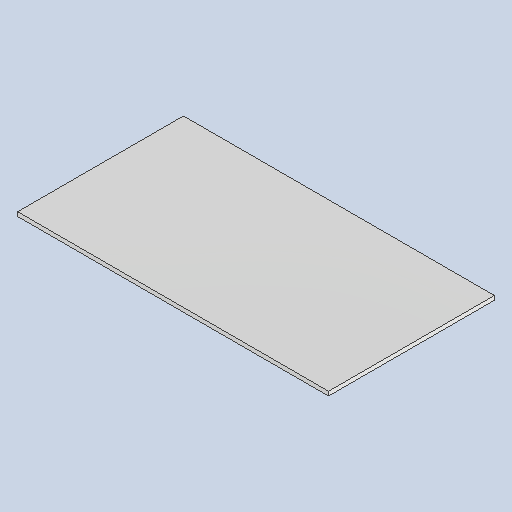
# Autodesk Inventor part: RDS-5002 Panel Plate 750x400
Saved by Autodesk Inventor 2026.2 (Build 302298000, 298)
## iProperties
Created: 2024-04-04
Part Number: RDS-5002 Panel Plate 750x400
Material: PVC, Unplasticized
Document SubType Name: Modeling
Designer: admin
Density: 1.29 g/cm^3
Appearance: Smooth - White
Mass: 3870 g
Surface Area: 6230 cm^2
Volume: 3000 cm^3
Stock Number: Пластина панельная (СДР 083)
Author: admin
Autodesk Inventor part; units mm, degrees
ref_plane "YZ Plane" through (0, 0, 0) normal (1, 0, 0) x (0, 1, 0)
ref_plane "XZ Plane" through (0, 0, 0) normal (0, 1, 0) x (-1, 0, 0)
ref_plane "XY Plane" through (0, 0, 0) normal (0, 0, 1) x (1, 0, 0)
sketch "Sketch1" plane through (0, 0, 0) normal (0, 0, 1) x (1, 0, 0)
  line L0 (-375, 200) -> (375, 200)
  line L1 (375, 200) -> (375, -200)
  line L2 (375, -200) -> (-375, -200)
  line L3 (-375, -200) -> (-375, 200)
  line L4 (-375, 200) -> (375, -200) construction
  line L5 (375, 200) -> (-375, -200) construction
  point P0 (0, 0)
  dimension "d0" = 750
  dimension "d1" = 400
  constraints: 12 end point, 2 midpoint, 2 parallel, 1 horizontal, 1 perpendicular
  measures "d0" distance of L1.end L2.end
  measures "d1" distance of L0.end L1.end
extrude "Extrusion1" add sketch "Sketch1" along normal blind 10
body "Solid1"
